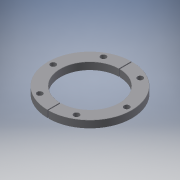
# Autodesk Inventor part: 15-0012-0325
Saved by Autodesk Inventor 2016 SP2 (Build 200236200, 236)
## iProperties
Created: 2017-10-30
Part Number: 15-0012-0325
Material: Generic
Document SubType Name: Modeling
Designer: jellerm1
Density: 0.001 g/cm^3
Appearance: Default
RuleStatus: InUse
BeforeDocSave0: Open Form
Author: jellerm1
Autodesk Inventor part; units mm, degrees
ref_plane "YZ Plane" through (0, 0, 0) normal (1, 0, 0) x (0, 1, 0)
ref_plane "XZ Plane" through (0, 0, 0) normal (0, 1, 0) x (-1, 0, 0)
ref_plane "XY Plane" through (0, 0, 0) normal (0, 0, 1) x (1, 0, 0)
sketch "Sketch1" plane through (0, 0, 0) normal (0, 0, 1) x (1, 0, 0)
  line L0 (0, 63) -> (0, -63) construction
  line L1 (-56, 0) -> (56, 0) construction
  circle A0 centre (0, 0) radius 28
  circle A1 centre (0, 0) radius 40
  line L2 (-0.5, -45) -> (0.5, -45)
  line L3 (0.5, -45) -> (0.5, 45)
  line L4 (0.5, 45) -> (-0.5, 45)
  line L5 (-0.5, 45) -> (-0.5, -45)
  line L6 (-0.5, -45) -> (0.5, 45) construction
  line L7 (0.5, -45) -> (-0.5, 45) construction
  point P0 (-35, 0)
  dimension "d0" = 56
  dimension "d1" = 80
  dimension "d2" = 35
  dimension "d15" = 1
  dimension "d16" = 90
  constraints: 12 end point, 2 centre point, 2 coincident, 2 midpoint, 2 parallel, 1 horizontal, 1 perpendicular, 1 point on line
  measures "d0" diameter of A0
  measures "d1" diameter of A1
  measures "d2" distance from line of L0 point (-35, 0)
  measures "d15" distance of L4.end L3.end
  measures "d16" distance of L3.end L2.end
extrude "Extrusion1" add sketch "Sketch1" against normal blind 7 contours A0 L3 A1 | A0 L5 A1 L3 | L3 A1 L5 A0 | A0 L5 A1
hole "Hole1" at (-35, 0, 0) direction (0, 0, -1) diameter 5.3 end through all
pattern_circular "Circular Pattern1" count 6 over 360 about axis through (0, 0, 0) along (0, 0, -1) of "Hole1"
chamfer "Chamfer1" distance 0.2 angle 45 4 edges at (-28, 0, 0) (-28, 0, -7) (-40, 0, 0) (-40, 0, -7)
extrude "Extrusion2" cut sketch "Sketch1" against normal through all contours L3 A0 L5 | A0 L5 A1 L3 | L3 A1 L5 A0 | A1 L5 L4 L3 | L3 L2 L5 A1
body "Solid1"
